Autodesk Fusion 360 part; units mm, degrees
(part 4 of 6)
sketch "Skizze7" plane through (0, 0, 0) normal (0, 1, 0) x (1, 0, 0)
  spline S0 degree 5 poles (100, -0.15) (99.9698, -0.1532) (99.9069, -0.1598) (99.8054, -0.1706) (99.6556, -0.1869) (99.4448, -0.2102) (99.2115, -0.2365) (98.9585, -0.2653) (98.6894, -0.2962) (98.4089, -0.3287) (98.1211, -0.3622) (97.8299, -0.3962) (97.5376, -0.4305) (97.2451, -0.4648) (96.9524, -0.4991) (96.6588, -0.5333) (96.3636, -0.5675) (96.0663, -0.6017) (95.7669, -0.6359) (95.4657, -0.6701) (95.1634, -0.7042) (94.8605, -0.7382) (94.5577, -0.7721) (94.2552, -0.8059) (93.9531, -0.8396) (93.6512, -0.8731) (93.3495, -0.9065) (93.0476, -0.9398) (92.7455, -0.973) (92.4431, -1.0061) (92.1403, -1.0391) (91.8374, -1.072) (91.5343, -1.1047) (91.2312, -1.1374) (90.9281, -1.1699) (90.625, -1.2023) (90.322, -1.2347) (90.019, -1.267) (89.7161, -1.2992) (89.4132, -1.3314) (89.1102, -1.3636) (88.8072, -1.3956) (88.5041, -1.4276) (88.2009, -1.4595) (87.8975, -1.4912) (87.5941, -1.5229) (87.2907, -1.5544) (86.9871, -1.5858) (86.6836, -1.6171) (86.3801, -1.6483) (86.0766, -1.6795) (85.7732, -1.7106) (85.4697, -1.7417) (85.1663, -1.7727) (84.8628, -1.8038) (84.5593, -1.8349) (84.2557, -1.8659) (83.9521, -1.8968) (83.6485, -1.9277) (83.3449, -1.9586) (83.0413, -1.9893) (82.7378, -2.02) (82.4342, -2.0506) (82.1306, -2.0811) (81.827, -2.1116) (81.5234, -2.142) (81.2197, -2.1725) (80.9161, -2.2029) (80.6124, -2.2334) (80.3086, -2.2637) (80.0049, -2.294) (79.7012, -2.3242) (79.3975, -2.3544) (79.0939, -2.3844) (78.7902, -2.4144) (78.4864, -2.4443) (78.1827, -2.4742) (77.8789, -2.5041) (77.5751, -2.5339) (77.2713, -2.5637) (76.9674, -2.5935) (76.6636, -2.6233) (76.3598, -2.6531) (76.0561, -2.6829) (75.7523, -2.7126) (75.4486, -2.7423) (75.1449, -2.7719) (74.8412, -2.8013) (74.5375, -2.8308) (74.2337, -2.8601) (73.93, -2.8894) (73.6262, -2.9186) (73.3225, -2.9478) (73.0187, -2.977) (72.7151, -3.0062) (72.4114, -3.0354) (72.1077, -3.0646) (71.8041, -3.0937) (71.5005, -3.1226) (71.1968, -3.1514) (70.8931, -3.1801) (70.5894, -3.2087) (70.2857, -3.2372) (69.982, -3.2656) (69.6783, -3.294) (69.3747, -3.3223) (69.071, -3.3505) (68.7674, -3.3787) (68.4638, -3.4069) (68.1603, -3.435) (67.8567, -3.463) (67.5532, -3.491) (67.2497, -3.5189) (66.9462, -3.5467) (66.6426, -3.5745) (66.3391, -3.6021) (66.0355, -3.6297) (65.7319, -3.6571) (65.4284, -3.6845) (65.1248, -3.7116) (64.8213, -3.7386) (64.5177, -3.7655) (64.2142, -3.7922) (63.9107, -3.8188) (63.6073, -3.8453) (63.3038, -3.8717) (63.0003, -3.8982) (62.6968, -3.9245) (62.3932, -3.9509) (62.0897, -3.9771) (61.7862, -4.0033) (61.4827, -4.0293) (61.1792, -4.0552) (60.8757, -4.0809) (60.5722, -4.1065) (60.2688, -4.1319) (59.9654, -4.1571) (59.662, -4.1823) (59.3586, -4.2073) (59.0552, -4.2323) (58.7519, -4.257) (58.4485, -4.2817) (58.1451, -4.3062) (57.8416, -4.3305) (57.5382, -4.3547) (57.2348, -4.3788) (56.9313, -4.4028) (56.6279, -4.4267) (56.3246, -4.4505) (56.0212, -4.4742) (55.7178, -4.4977) (55.4145, -4.5211) (55.1112, -4.5442) (54.8078, -4.5671) (54.5044, -4.5897) (54.201, -4.6121) (53.8976, -4.6343) (53.5942, -4.6565) (53.2908, -4.6785) (52.9874, -4.7005) (52.6841, -4.7225) (52.3808, -4.7443) (52.0775, -4.7661) (51.7742, -4.7877) (51.4709, -4.809) (51.1676, -4.83) (50.8643, -4.8508) (50.561, -4.8712) (50.2577, -4.8915) (49.9545, -4.9115) (49.6512, -4.9314) (49.348, -4.9511) (49.0448, -4.9707) (48.7416, -4.9902) (48.4384, -5.0096) (48.1352, -5.0289) (47.832, -5.048) (47.5287, -5.067) (47.2255, -5.0857) (46.9222, -5.1042) (46.619, -5.1224) (46.3158, -5.1403) (46.0126, -5.1578) (45.7095, -5.1752) (45.4065, -5.1922) (45.1034, -5.2091) (44.8004, -5.2257) (44.4974, -5.2422) (44.1943, -5.2585) (43.8913, -5.2747) (43.5883, -5.2906) (43.2852, -5.3063) (42.9822, -5.3218) (42.6791, -5.3371) (42.376, -5.352) (42.0729, -5.3668) (41.7699, -5.3812) (41.4668, -5.3954) (41.1639, -5.4093) (40.8609, -5.423) (40.558, -5.4364) (40.2551, -5.4495) (39.9523, -5.4623) (39.6494, -5.4749) (39.3467, -5.4871) (39.0439, -5.4992) (38.7411, -5.511) (38.4384, -5.5225) (38.1357, -5.5338) (37.833, -5.5448) (37.5303, -5.5556) (37.2276, -5.566) (36.9249, -5.5762) (36.6223, -5.586) (36.3195, -5.5955) (36.0169, -5.6046) (35.7142, -5.6134) (35.4116, -5.6218) (35.109, -5.6299) (34.8065, -5.6376) (34.5041, -5.645) (34.2017, -5.6521) (33.8993, -5.6588) (33.597, -5.6653) (33.2947, -5.6714) (32.9923, -5.6771) (32.69, -5.6826) (32.3877, -5.6877) (32.0854, -5.6924) (31.7831, -5.6968) (31.4809, -5.7008) (31.1788, -5.7044) (30.8767, -5.7077) (30.5747, -5.7105) (30.2727, -5.713) (29.9708, -5.7151) (29.6689, -5.7167) (29.367, -5.718) (29.0651, -5.7188) (28.7633, -5.7192) (28.4615, -5.7192) (28.1597, -5.7188) (27.858, -5.718) (27.5564, -5.7168) (27.2548, -5.7152) (26.9533, -5.7132) (26.652, -5.7108) (26.3507, -5.708) (26.0495, -5.7047) (25.7484, -5.701) (25.4474, -5.6967) (25.1464, -5.6918) (24.8455, -5.6863) (24.5447, -5.6803) (24.2439, -5.6737) (23.9432, -5.6666) (23.6427, -5.659) (23.3422, -5.6509) (23.0419, -5.6424) (22.7418, -5.6333) (22.4418, -5.6237) (22.1419, -5.6136) (21.8422, -5.6028) (21.5426, -5.5913) (21.2432, -5.5792) (20.9438, -5.5665) (20.6446, -5.5531) (20.3455, -5.5391) (20.0466, -5.5244) (19.7477, -5.5091) (19.4491, -5.4931) (19.1507, -5.4765) (18.8524, -5.4591) (18.5545, -5.4409) (18.2568, -5.422) (17.9594, -5.4023) (17.6622, -5.3817) (17.3652, -5.3603) (17.0684, -5.3381) (16.7718, -5.315) (16.4753, -5.2911) (16.1791, -5.2663) (15.8831, -5.2407) (15.5874, -5.2142) (15.2919, -5.1867) (14.9968, -5.1584) (14.702, -5.1291) (14.4076, -5.0988) (14.1136, -5.0674) (13.8201, -5.0351) (13.5269, -5.0016) (13.2341, -4.9671) (12.9417, -4.9315) (12.6498, -4.8948) (12.3582, -4.857) (12.0671, -4.818) (11.7764, -4.7779) (11.4862, -4.7365) (11.1965, -4.6938) (10.9075, -4.6497) (10.6192, -4.6043) (10.3315, -4.5575) (10.0447, -4.5093) (9.7585, -4.4596) (9.4732, -4.4085) (9.1887, -4.356) (8.9051, -4.302) (8.6225, -4.2465) (8.3408, -4.1894) (8.0602, -4.1305) (7.7808, -4.0699) (7.5027, -4.0075) (7.226, -3.9431) (6.9507, -3.8769) (6.677, -3.8087) (6.4051, -3.7385) (6.135, -3.6664) (5.8669, -3.5922) (5.6011, -3.5159) (5.3377, -3.4374) (5.0769, -3.3567) (4.819, -3.2736) (4.5643, -3.1883) (4.3131, -3.1008) (4.0657, -3.011) (3.8225, -2.9191) (3.5839, -2.8252) (3.3505, -2.7292) (3.1226, -2.6313) (2.9008, -2.5315) (2.6856, -2.4301) (2.4774, -2.3275) (2.2767, -2.2241) (2.0839, -2.1203) (1.8992, -2.0164) (1.7229, -1.9124) (1.5554, -1.8083) (1.3968, -1.7039) (1.2471, -1.5995) (1.1063, -1.4957) (0.9742, -1.3933) (0.8506, -1.2926) (0.7354, -1.1923) (0.6286, -1.0909) (0.53, -0.9884) (0.4394, -0.888) (0.3563, -0.7927) (0.281, -0.6986) (0.2138, -0.5963) (0.1548, -0.487) (0.1038, -0.3939) (0.0606, -0.3221) (0.0271, -0.2204) (0.0055, -0.0625) (-0.0028, 0.0091) (-0.0003, -0.0252) (0.0079, 0.0969) (0.0316, 0.2301) (0.0746, 0.3075) (0.1323, 0.3792) (0.2013, 0.4693) (0.2805, 0.5567) (0.3689, 0.6311) (0.4651, 0.7007) (0.5684, 0.7731) (0.6792, 0.8469) (0.798, 0.9188) (0.925, 0.9876) (1.0603, 1.0544) (1.2038, 1.1205) (1.3558, 1.1861) (1.5166, 1.2512) (1.6866, 1.3155) (1.8657, 1.3788) (2.0541, 1.441) (2.2515, 1.5019) (2.4577, 1.5615) (2.6724, 1.6197) (2.8953, 1.6763) (3.1259, 1.7312) (3.3638, 1.7844) (3.6084, 1.8358) (3.8593, 1.8852) (4.116, 1.9326) (4.3778, 1.978) (4.6442, 2.0215) (4.9147, 2.0631) (5.1886, 2.1031) (5.4656, 2.1415) (5.7452, 2.1784) (6.0271, 2.2138) (6.311, 2.2478) (6.5966, 2.2804) (6.8839, 2.3115) (7.1726, 2.3413) (7.4625, 2.3698) (7.7535, 2.3969) (8.0455, 2.4229) (8.3383, 2.4477) (8.6319, 2.4715) (8.926, 2.4943) (9.2208, 2.5161) (9.516, 2.5371) (9.8118, 2.5573) (10.1081, 2.5766) (10.4048, 2.5951) (10.702, 2.6128) (10.9995, 2.6297) (11.2974, 2.6459) (11.5957, 2.6612) (11.8942, 2.6758) (12.1931, 2.6897) (12.4922, 2.7029) (12.7915, 2.7155) (13.0911, 2.7274) (13.3908, 2.7387) (13.6908, 2.7495) (13.991, 2.7597) (14.2914, 2.7694) (14.592, 2.7786) (14.8927, 2.7873) (15.1936, 2.7956) (15.4947, 2.8034) (15.7959, 2.8107) (16.0972, 2.8176) (16.3986, 2.8241) (16.7001, 2.8301) (17.0017, 2.8357) (17.3034, 2.8408) (17.6052, 2.8455) (17.9071, 2.8497) (18.2091, 2.8535) (18.5113, 2.8569) (18.8135, 2.8599) (19.1159, 2.8626) (19.4183, 2.8649) (19.7208, 2.867) (20.0233, 2.8687) (20.3259, 2.8702) (20.6285, 2.8714) (20.9313, 2.8723) (21.2341, 2.8729) (21.537, 2.8732) (21.8401, 2.8731) (22.1432, 2.8727) (22.4464, 2.872) (22.7496, 2.8711) (23.0529, 2.87) (23.3562, 2.8687) (23.6595, 2.8672) (23.9628, 2.8655) (24.2662, 2.8635) (24.5695, 2.8612) (24.873, 2.8586) (25.1764, 2.8557) (25.4799, 2.8526) (25.7834, 2.8491) (26.087, 2.8455) (26.3906, 2.8417) (26.6942, 2.8377) (26.9979, 2.8335) (27.3016, 2.8292) (27.6053, 2.8247) (27.909, 2.8199) (28.2128, 2.815) (28.5166, 2.8098) (28.8204, 2.8044) (29.1243, 2.7989) (29.4282, 2.7931) (29.7322, 2.7872) (30.0362, 2.7811) (30.3402, 2.7749) (30.6443, 2.7685) (30.9483, 2.762) (31.2524, 2.7553) (31.5565, 2.7485) (31.8605, 2.7415) (32.1646, 2.7343) (32.4688, 2.727) (32.7729, 2.7194) (33.0771, 2.7116) (33.3814, 2.7037) (33.6857, 2.6956) (33.99, 2.6873) (34.2943, 2.679) (34.5986, 2.6706) (34.9029, 2.6621) (35.2072, 2.6536) (35.5115, 2.6449) (35.8158, 2.6362) (36.1201, 2.6272) (36.4244, 2.6181) (36.7287, 2.6088) (37.033, 2.5992) (37.3374, 2.5896) (37.6418, 2.5797) (37.9462, 2.5698) (38.2506, 2.5597) (38.555, 2.5497) (38.8595, 2.5395) (39.1639, 2.5293) (39.4684, 2.519) (39.7729, 2.5086) (40.0774, 2.4981) (40.382, 2.4874) (40.6865, 2.4767) (40.9911, 2.4658) (41.2956, 2.4548) (41.6001, 2.4437) (41.9046, 2.4325) (42.2091, 2.4213) (42.5136, 2.4099) (42.8182, 2.3985) (43.1227, 2.3871) (43.4273, 2.3756) (43.7319, 2.3641) (44.0365, 2.3525) (44.3412, 2.3407) (44.6458, 2.3289) (44.9504, 2.3169) (45.255, 2.3047) (45.5596, 2.2923) (45.8641, 2.2798) (46.1687, 2.2673) (46.4734, 2.2546) (46.778, 2.2419) (47.0827, 2.2291) (47.3874, 2.2163) (47.6921, 2.2036) (47.9968, 2.1909) (48.3015, 2.1781) (48.6061, 2.1654) (48.9108, 2.1526) (49.2155, 2.1396) (49.5202, 2.1265) (49.8248, 2.1133) (50.1295, 2.0999) (50.4341, 2.0863) (50.7388, 2.0725) (51.0434, 2.0588) (51.3481, 2.0449) (51.6528, 2.0311) (51.9575, 2.0173) (52.2622, 2.0035) (52.567, 1.9897) (52.8718, 1.9759) (53.1766, 1.962) (53.4814, 1.948) (53.7863, 1.9339) (54.0912, 1.9197) (54.396, 1.9054) (54.7008, 1.891) (55.0055, 1.8766) (55.3102, 1.862) (55.6149, 1.8475) (55.9196, 1.8329) (56.2244, 1.8183) (56.5292, 1.8037) (56.834, 1.789) (57.139, 1.7744) (57.4439, 1.7597) (57.7489, 1.7449) (58.0538, 1.7301) (58.3586, 1.7151) (58.6635, 1.7001) (58.9683, 1.685) (59.273, 1.6699) (59.5778, 1.6547) (59.8826, 1.6395) (60.1875, 1.6242) (60.4923, 1.609) (60.7972, 1.5937) (61.1022, 1.5784) (61.4071, 1.5631) (61.7121, 1.5478) (62.017, 1.5324) (62.322, 1.5169) (62.627, 1.5014) (62.932, 1.4859) (63.237, 1.4704) (63.5421, 1.4549) (63.8472, 1.4393) (64.1522, 1.4237) (64.4573, 1.408) (64.7624, 1.3923) (65.0675, 1.3765) (65.3726, 1.3607) (65.6776, 1.3449) (65.9827, 1.3291) (66.2877, 1.3133) (66.5928, 1.2974) (66.8979, 1.2816) (67.203, 1.2658) (67.5081, 1.2501) (67.8131, 1.2342) (68.1182, 1.2184) (68.4232, 1.2026) (68.7282, 1.1867) (69.0331, 1.1709) (69.3381, 1.1551) (69.643, 1.1393) (69.948, 1.1236) (70.253, 1.1079) (70.558, 1.0923) (70.863, 1.0767) (71.168, 1.0611) (71.4729, 1.0454) (71.7779, 1.0298) (72.0828, 1.0141) (72.3876, 0.9984) (72.6925, 0.9828) (72.9974, 0.9672) (73.3023, 0.9516) (73.6072, 0.9362) (73.9121, 0.9209) (74.217, 0.9056) (74.5219, 0.8904) (74.8268, 0.8753) (75.1316, 0.8602) (75.4364, 0.8452) (75.7411, 0.8301) (76.0458, 0.815) (76.3504, 0.7999) (76.6551, 0.7847) (76.9597, 0.7696) (77.2643, 0.7545) (77.569, 0.7396) (77.8736, 0.7247) (78.1782, 0.7101) (78.4828, 0.6956) (78.7874, 0.6812) (79.092, 0.667) (79.3966, 0.6529) (79.7011, 0.6389) (80.0055, 0.6249) (80.31, 0.6109) (80.6144, 0.5969) (80.9188, 0.583) (81.2231, 0.5692) (81.5274, 0.5556) (81.8317, 0.5421) (82.136, 0.5288) (82.4402, 0.5157) (82.7444, 0.5027) (83.0486, 0.4897) (83.3527, 0.4769) (83.6567, 0.4641) (83.9608, 0.4514) (84.2648, 0.4388) (84.5688, 0.4263) (84.8728, 0.414) (85.1769, 0.4018) (85.4809, 0.3898) (85.7849, 0.378) (86.0889, 0.3665) (86.3928, 0.3551) (86.6966, 0.344) (87.0004, 0.3332) (87.3041, 0.3225) (87.6078, 0.3119) (87.9114, 0.3015) (88.2151, 0.2912) (88.5187, 0.281) (88.8224, 0.271) (89.126, 0.2612) (89.4295, 0.2516) (89.7329, 0.2423) (90.0362, 0.2333) (90.3395, 0.2246) (90.6426, 0.2162) (90.9458, 0.2081) (91.2489, 0.2001) (91.5521, 0.1924) (91.8553, 0.1848) (92.1584, 0.1775) (92.4612, 0.1704) (92.7638, 0.1635) (93.0659, 0.1571) (93.3677, 0.151) (93.6691, 0.1453) (93.9705, 0.1401) (94.2719, 0.1353) (94.5735, 0.1308) (94.8753, 0.1267) (95.1771, 0.123) (95.4782, 0.1197) (95.7781, 0.1167) (96.0762, 0.1143) (96.3721, 0.1124) (96.6657, 0.111) (96.9575, 0.1103) (97.2484, 0.1103) (97.5392, 0.1111) (97.83, 0.1126) (98.12, 0.1148) (98.407, 0.1178) (98.6872, 0.1213) (98.9562, 0.1253) (99.2095, 0.1298) (99.4431, 0.1345) (99.6545, 0.1395) (99.8047, 0.1436) (99.9066, 0.1468) (99.9697, 0.1489) (100, 0.15) knots 0 0 0 0 0 0 0.00142857 0.00285714 0.00428571 0.00571429 0.00714286 0.00857143 0.01 0.01142857 0.01285714 0.01428571 0.01571429 0.01714286 0.01857143 0.02 0.02142857 0.02285714 0.02428571 0.02571429 0.02714286 0.02857143 0.03 0.03142857 0.03285714 0.03428571 0.03571429 0.03714286 0.03857143 0.04 0.04142857 0.04285714 0.04428571 0.04571429 0.04714286 0.04857143 0.05 0.05142857 0.05285714 0.05428571 0.05571429 0.05714286 0.05857143 0.06 0.06142857 0.06285714 0.06428571 0.06571429 0.06714286 0.06857143 0.07 0.07142857 0.07285714 0.07428571 0.07571429 0.07714286 0.07857143 0.08 0.08142857 0.08285714 0.08428571 0.08571429 0.08714286 0.08857143 0.09 0.09142857 0.09285714 0.09428571 0.09571429 0.09714286 0.09857143 0.1 0.10142857 0.10285714 0.10428571 0.10571429 0.10714286 0.10857143 0.11 0.11142857 0.11285714 0.11428571 0.11571429 0.11714286 0.11857143 0.12 0.12142857 0.12285714 0.12428571 0.12571429 0.12714286 0.12857143 0.13 0.13142857 0.13285714 0.13428571 0.13571429 0.13714286 0.13857143 0.14 0.14142857 0.14285714 0.14428571 0.14571429 0.14714286 0.14857143 0.15 0.15142857 0.15285714 0.15428571 0.15571429 0.15714286 0.15857143 0.16 0.16142857 0.16285714 0.16428571 0.16571429 0.16714286 0.16857143 0.17 0.17142857 0.17285714 0.17428571 0.17571429 0.17714286 0.17857143 0.18 0.18142857 0.18285714 0.18428571 0.18571429 0.18714286 0.18857143 0.19 0.19142857 0.19285714 0.19428571 0.19571429 0.19714286 0.19857143 0.2 0.20142857 0.20285714 0.20428571 0.20571429 0.20714286 0.20857143 0.21 0.21142857 0.21285714 0.21428571 0.21571429 0.21714286 0.21857143 0.22 0.22142857 0.22285714 0.22428571 0.22571429 0.22714286 0.22857143 0.23 0.23142857 0.23285714 0.23428571 0.23571429 0.23714286 0.23857143 0.24 0.24142857 0.24285714 0.24428571 0.24571429 0.24714286 0.24857143 0.25 0.25142857 0.25285714 0.25428571 0.25571429 0.25714286 0.25857143 0.26 0.26142857 0.26285714 0.26428571 0.26571429 0.26714286 0.26857143 0.27 0.27142857 0.27285714 0.27428571 0.27571429 0.27714286 0.27857143 0.28 0.28142857 0.28285714 0.28428571 0.28571429 0.28714286 0.28857143 0.29 0.29142857 0.29285714 0.29428571 0.29571429 0.29714286 0.29857143 0.3 0.30142857 0.30285714 0.30428571 0.30571429 0.30714286 0.30857143 0.31 0.31142857 0.31285714 0.31428571 0.31571429 0.31714286 0.31857143 0.32 0.32142857 0.32285714 0.32428571 0.32571429 0.32714286 0.32857143 0.33 0.33142857 0.33285714 0.33428571 0.33571429 0.33714286 0.33857143 0.34 0.34142857 0.34285714 0.34428571 0.34571429 0.34714286 0.34857143 0.35 0.35142857 0.35285714 0.35428571 0.35571429 0.35714286 0.35857143 0.36 0.36142857 0.36285714 0.36428571 0.36571429 0.36714286 0.36857143 0.37 0.37142857 0.37285714 0.37428571 0.37571429 0.37714286 0.37857143 0.38 0.38142857 0.38285714 0.38428571 0.38571429 0.38714286 0.38857143 0.39 0.39142857 0.39285714 0.39428571 0.39571429 0.39714286 0.39857143 0.4 0.40142857 0.40285714 0.40428571 0.40571429 0.40714286 0.40857143 0.41 0.41142857 0.41285714 0.41428571 0.41571429 0.41714286 0.41857143 0.42 0.42142857 0.42285714 0.42428571 0.42571429 0.42714286 0.42857143 0.43 0.43142857 0.43285714 0.43428571 0.43571429 0.43714286 0.43857143 0.44 0.44142857 0.44285714 0.44428571 0.44571429 0.44714286 0.44857143 0.45 0.45142857 0.45285714 0.45428571 0.45571429 0.45714286 0.45857143 0.46 0.46142857 0.46285714 0.46428571 0.46571429 0.46714286 0.46857143 0.47 0.47142857 0.47285714 0.47428571 0.47571429 0.47714286 0.47857143 0.48 0.48142857 0.48285714 0.48428571 0.48571429 0.48714286 0.48857143 0.49 0.49142857 0.49285714 0.49428571 0.49571429 0.49714286 0.49857143 0.5 0.50142857 0.50285714 0.50428571 0.50571429 0.50714286 0.50857143 0.51 0.51142857 0.51285714 0.51428571 0.51571429 0.51714286 0.51857143 0.52 0.52142857 0.52285714 0.52428571 0.52571429 0.52714286 0.52857143 0.53 0.53142857 0.53285714 0.53428571 0.53571429 0.53714286 0.53857143 0.54 0.54142857 0.54285714 0.54428571 0.54571429 0.54714286 0.54857143 0.55 0.55142857 0.55285714 0.55428571 0.55571429 0.55714286 0.55857143 0.56 0.56142857 0.56285714 0.56428571 0.56571429 0.56714286 0.56857143 0.57 0.57142857 0.57285714 0.57428571 0.57571429 0.57714286 0.57857143 0.58 0.58142857 0.58285714 0.58428571 0.58571429 0.58714286 0.58857143 0.59 0.59142857 0.59285714 0.59428571 0.59571429 0.59714286 0.59857143 0.6 0.60142857 0.60285714 0.60428571 0.60571429 0.60714286 0.60857143 0.61 0.61142857 0.61285714 0.61428571 0.61571429 0.61714286 0.61857143 0.62 0.62142857 0.62285714 0.62428571 0.62571429 0.62714286 0.62857143 0.63 0.63142857 0.63285714 0.63428571 0.63571429 0.63714286 0.63857143 0.64 0.64142857 0.64285714 0.64428571 0.64571429 0.64714286 0.64857143 0.65 0.65142857 0.65285714 0.65428571 0.65571429 0.65714286 0.65857143 0.66 0.66142857 0.66285714 0.66428571 0.66571429 0.66714286 0.66857143 0.67 0.67142857 0.67285714 0.67428571 0.67571429 0.67714286 0.67857143 0.68 0.68142857 0.68285714 0.68428571 0.68571429 0.68714286 0.68857143 0.69 0.69142857 0.69285714 0.69428571 0.69571429 0.69714286 0.69857143 0.7 0.70142857 0.70285714 0.70428571 0.70571429 0.70714286 0.70857143 0.71 0.71142857 0.71285714 0.71428571 0.71571429 0.71714286 0.71857143 0.72 0.72142857 0.72285714 0.72428571 0.72571429 0.72714286 0.72857143 0.73 0.73142857 0.73285714 0.73428571 0.73571429 0.73714286 0.73857143 0.74 0.74142857 0.74285714 0.74428571 0.74571429 0.74714286 0.74857143 0.75 0.75142857 0.75285714 0.75428571 0.75571429 0.75714286 0.75857143 0.76 0.76142857 0.76285714 0.76428571 0.76571429 0.76714286 0.76857143 0.77 0.77142857 0.77285714 0.77428571 0.77571429 0.77714286 0.77857143 0.78 0.78142857 0.78285714 0.78428571 0.78571429 0.78714286 0.78857143 0.79 0.79142857 0.79285714 0.79428571 0.79571429 0.79714286 0.79857143 0.8 0.80142857 0.80285714 0.80428571 0.80571429 0.80714286 0.80857143 0.81 0.81142857 0.81285714 0.81428571 0.81571429 0.81714286 0.81857143 0.82 0.82142857 0.82285714 0.82428571 0.82571429 0.82714286 0.82857143 0.83 0.83142857 0.83285714 0.83428571 0.83571429 0.83714286 0.83857143 0.84 0.84142857 0.84285714 0.84428571 0.84571429 0.84714286 0.84857143 0.85 0.85142857 0.85285714 0.85428571 0.85571429 0.85714286 0.85857143 0.86 0.86142857 0.86285714 0.86428571 0.86571429 0.86714286 0.86857143 0.87 0.87142857 0.87285714 0.87428571 0.87571429 0.87714286 0.87857143 0.88 0.88142857 0.88285714 0.88428571 0.88571429 0.88714286 0.88857143 0.89 0.89142857 0.89285714 0.89428571 0.89571429 0.89714286 0.89857143 0.9 0.90142857 0.90285714 0.90428571 0.90571429 0.90714286 0.90857143 0.91 0.91142857 0.91285714 0.91428571 0.91571429 0.91714286 0.91857143 0.92 0.92142857 0.92285714 0.92428571 0.92571429 0.92714286 0.92857143 0.93 0.93142857 0.93285714 0.93428571 0.93571429 0.93714286 0.93857143 0.94 0.94142857 0.94285714 0.94428571 0.94571429 0.94714286 0.94857143 0.95 0.95142857 0.95285714 0.95428571 0.95571429 0.95714286 0.95857143 0.96 0.96142857 0.96285714 0.96428571 0.96571429 0.96714286 0.96857143 0.97 0.97142857 0.97285714 0.97428571 0.97571429 0.97714286 0.97857143 0.98 0.98142857 0.98285714 0.98428571 0.98571429 0.98714286 0.98857143 0.99 0.99142857 0.99285714 0.99428571 0.99571429 0.99714286 0.99857143 1 1 1 1 1 1
  line L0 (100, 0.15) -> (100, -0.15)
  point P0 (99.314, -0.225)
  point P1 (97.986, -0.378)
  point P2 (96.428, -0.56)
  point P3 (94.791, -0.746)
  point P4 (93.136, -0.93)
  point P5 (91.476, -1.111)
  point P6 (89.812, -1.289)
  point P7 (88.148, -1.465)
  point P8 (86.48, -1.638)
  point P9 (84.812, -1.809)
  point P10 (83.143, -1.979)
  point P11 (81.474, -2.147)
  point P12 (79.804, -2.314)
  point P13 (78.134, -2.479)
  point P14 (76.463, -2.643)
  point P15 (74.793, -2.806)
  point P16 (73.123, -2.967)
  point P17 (71.454, -3.127)
  point P18 (69.785, -3.284)
  point P19 (68.117, -3.439)
  point P20 (66.45, -3.592)
  point P21 (64.783, -3.742)
  point P22 (63.117, -3.888)
  point P23 (61.451, -4.032)
  point P24 (59.786, -4.172)
  point P25 (58.122, -4.308)
  point P26 (56.458, -4.44)
  point P27 (54.795, -4.568)
  point P28 (53.132, -4.69)
  point P29 (51.47, -4.809)
  point P30 (49.809, -4.921)
  point P31 (48.149, -5.028)
  point P32 (46.489, -5.13)
  point P33 (44.831, -5.224)
  point P34 (43.174, -5.312)
  point P35 (41.517, -5.393)
  point P36 (39.862, -5.466)
  point P37 (38.209, -5.531)
  point P38 (36.557, -5.588)
  point P39 (34.906, -5.635)
  point P40 (33.258, -5.672)
  point P41 (31.611, -5.699)
  point P42 (29.967, -5.715)
  point P43 (28.325, -5.719)
  point P44 (26.686, -5.711)
  point P45 (25.052, -5.69)
  point P46 (23.422, -5.653)
  point P47 (21.799, -5.601)
  point P48 (20.183, -5.531)
  point P49 (18.575, -5.442)
  point P50 (16.979, -5.331)
  point P51 (15.393, -5.196)
  point P52 (13.822, -5.035)
  point P53 (12.27, -4.845)
  point P54 (10.739, -4.623)
  point P55 (9.239, -4.365)
  point P56 (7.779, -4.069)
  point P57 (6.375, -3.73)
  point P58 (5.052, -3.348)
  point P59 (3.848, -2.928)
  point P60 (2.814, -2.49)
  point P61 (1.992, -2.068)
  point P62 (1.38, -1.691)
  point P63 (0.938, -1.363)
  point P64 (0.619, -1.079)
  point P65 (0.387, -0.827)
  point P66 (0.219, -0.6)
  point P67 (0.102, -0.392)
  point P68 (0.028, -0.198)
  point P69 (0, -0.016)
  point P70 (0.022, 0.161)
  point P71 (0.102, 0.34)
  point P72 (0.243, 0.513)
  point P73 (0.44, 0.682)
  point P74 (0.698, 0.857)
  point P75 (1.039, 1.043)
  point P76 (1.496, 1.242)
  point P77 (2.124, 1.462)
  point P78 (2.98, 1.696)
  point P79 (4.089, 1.927)
  point P80 (5.414, 2.134)
  point P81 (6.873, 2.31)
  point P82 (8.406, 2.453)
  point P83 (9.978, 2.568)
  point P84 (11.575, 2.66)
  point P85 (13.189, 2.731)
  point P86 (14.815, 2.785)
  point P87 (16.45, 2.825)
  point P88 (18.091, 2.852)
  point P89 (19.738, 2.867)
  point P90 (21.389, 2.873)
  point P91 (23.045, 2.87)
  point P92 (24.703, 2.86)
  point P93 (26.363, 2.842)
  point P94 (28.025, 2.818)
  point P95 (29.689, 2.788)
  point P96 (31.355, 2.753)
  point P97 (33.022, 2.713)
  point P98 (34.691, 2.668)
  point P99 (36.36, 2.62)
  point P100 (38.03, 2.567)
  point P101 (39.701, 2.511)
  point P102 (41.373, 2.452)
  point P103 (43.045, 2.39)
  point P104 (44.718, 2.326)
  point P105 (46.391, 2.258)
  point P106 (48.065, 2.188)
  point P107 (49.739, 2.117)
  point P108 (51.413, 2.042)
  point P109 (53.088, 1.966)
  point P110 (54.764, 1.888)
  point P111 (56.439, 1.808)
  point P112 (58.116, 1.727)
  point P113 (59.792, 1.644)
  point P114 (61.469, 1.56)
  point P115 (63.147, 1.475)
  point P116 (64.826, 1.389)
  point P117 (66.505, 1.302)
  point P118 (68.184, 1.215)
  point P119 (69.862, 1.128)
  point P120 (71.54, 1.042)
  point P121 (73.217, 0.956)
  point P122 (74.894, 0.872)
  point P123 (76.569, 0.789)
  point P124 (78.243, 0.707)
  point P125 (79.916, 0.629)
  point P126 (81.587, 0.553)
  point P127 (83.256, 0.481)
  point P128 (84.923, 0.412)
  point P129 (86.589, 0.348)
  point P130 (88.252, 0.29)
  point P131 (89.913, 0.237)
  point P132 (91.57, 0.192)
  point P133 (93.221, 0.154)
  point P134 (94.86, 0.127)
  point P135 (96.471, 0.112)
  point P136 (98.001, 0.114)
  point P137 (99.315, 0.132)
surface "Profilschnitt_R3" add patch profiles "Skizze7" section 1 separate body makes body 7
scale "Profiltiefe_R3" factor 1.05 about (0, 0, 0) bodies 7
move_body "Station_R3" bodies 7 to x (1, 0, 0) y (0, 1, 0) z (0, 0, 1) at (0, 1279.8142, 21.2919)
loft "Fluegelsegment_L1" add section 1 face at (94.3234, 0, 0.5477) section 2 face at (94.3234, -60, 0.5477) separate body on bodies 1 2 makes body 8
loft "Fluegelsegment_L2" add section 1 face at (94.3234, -60, 0.5477) section 2 face at (61.0067, -669.9071, 11.0551) separate body on bodies 2 3 makes body 9
loft "Fluegelsegment_L3" add section 1 face at (61.0067, -669.9071, 11.0551) section 2 face at (31.5807, -1279.8142, 21.5024) separate body on bodies 3 4 makes body 10
loft "Fluegelsegment_R1" add section 1 face at (94.3234, 0, 0.5477) section 2 face at (94.3234, 60, 0.5477) separate body on bodies 1 5 makes body 11
loft "Fluegelsegment_R2" add section 1 face at (94.3234, 60, 0.5477) section 2 face at (61.0067, 669.9071, 11.0551) separate body on bodies 5 6 makes body 12
loft "Fluegelsegment_R3" add section 1 face at (61.0067, 669.9071, 11.0551) section 2 face at (31.5807, 1279.8142, 21.5024) separate body on bodies 6 7 makes body 13
combine "Alle_Fluegelsegmente_verbinden" operation add target body 8 tool bodies 9 10 11 12 13
delete_body "Körper entfernen1" bodies 1
delete_body "Körper entfernen2" bodies 2
delete_body "Körper entfernen3" bodies 3
delete_body "Körper entfernen4" bodies 4
delete_body "Körper entfernen5" bodies 5
delete_body "Körper entfernen6" bodies 6
delete_body "Körper entfernen7" bodies 7
sketch "Skizze8" plane through (0, 0, 0) normal (0, 1, 0) x (1, 0, 0)
  spline S0 degree 5 poles (100, 0) (99.9599, -0.0026) (99.8783, -0.0078) (99.7514, -0.0159) (99.5736, -0.0272) (99.3368, -0.0422) (99.0859, -0.058) (98.8215, -0.0747) (98.5446, -0.0922) (98.2562, -0.1105) (97.9576, -0.1296) (97.6501, -0.1494) (97.3347, -0.1698) (97.0124, -0.1908) (96.6841, -0.2122) (96.3507, -0.2339) (96.013, -0.256) (95.6718, -0.2783) (95.328, -0.3008) (94.9821, -0.3235) (94.6349, -0.3465) (94.2867, -0.3695) (93.9378, -0.3928) (93.5884, -0.4161) (93.2386, -0.4396) (92.8883, -0.4632) (92.5376, -0.4869) (92.1865, -0.5106) (91.8352, -0.5344) (91.4836, -0.5582) (91.1319, -0.5821) (90.7802, -0.606) (90.4285, -0.6299) (90.0769, -0.6539) (89.7253, -0.678) (89.3737, -0.7023) (89.022, -0.7267) (88.6703, -0.7512) (88.3186, -0.7759) (87.9668, -0.8006) (87.6149, -0.8254) (87.263, -0.8502) (86.9111, -0.8749) (86.5592, -0.8995) (86.2073, -0.9241) (85.8554, -0.9488) (85.5035, -0.9735) (85.1516, -0.9983) (84.7997, -1.0232) (84.4478, -1.0482) (84.096, -1.0733) (83.7441, -1.0984) (83.3921, -1.1236) (83.0402, -1.1487) (82.6882, -1.1738) (82.3362, -1.1989) (81.9842, -1.2239) (81.6322, -1.2489) (81.2802, -1.2739) (80.9282, -1.2989) (80.5763, -1.3239) (80.2243, -1.3489) (79.8723, -1.374) (79.5203, -1.3991) (79.1682, -1.4243) (78.8161, -1.4495) (78.464, -1.4747) (78.1119, -1.5) (77.7598, -1.5252) (77.4078, -1.5505) (77.0559, -1.5758) (76.704, -1.601) (76.3522, -1.6263) (76.0003, -1.6515) (75.6485, -1.6767) (75.2966, -1.7019) (74.9448, -1.727) (74.5929, -1.7521) (74.2409, -1.7771) (73.889, -1.802) (73.5371, -1.8269) (73.1851, -1.8516) (72.8332, -1.8763) (72.4813, -1.901) (72.1294, -1.9256) (71.7776, -1.9501) (71.4257, -1.9746) (71.0739, -1.9991) (70.7221, -2.0236) (70.3703, -2.0481) (70.0185, -2.0726) (69.6667, -2.0971) (69.3149, -2.1216) (68.9631, -2.146) (68.6113, -2.1702) (68.2594, -2.1944) (67.9075, -2.2184) (67.5557, -2.2422) (67.2038, -2.266) (66.852, -2.2897) (66.5001, -2.3133) (66.1483, -2.337) (65.7966, -2.3607) (65.4448, -2.3844) (65.0931, -2.4081) (64.7414, -2.4316) (64.3896, -2.455) (64.0378, -2.4783) (63.686, -2.5013) (63.3342, -2.5241) (62.9824, -2.5469) (62.6307, -2.5695) (62.2789, -2.592) (61.9273, -2.6145) (61.5756, -2.637) (61.2239, -2.6595) (60.8722, -2.6819) (60.5205, -2.7044) (60.1687, -2.7268) (59.8169, -2.7491) (59.4651, -2.7713) (59.1133, -2.7933) (58.7615, -2.8151) (58.4097, -2.8366) (58.058, -2.858) (57.7063, -2.8792) (57.3545, -2.9002) (57.0028, -2.9212) (56.651, -2.9422) (56.2992, -2.9632) (55.9474, -2.9841) (55.5955, -3.0049) (55.2436, -3.0257) (54.8918, -3.0462) (54.54, -3.0667) (54.1882, -3.0869) (53.8365, -3.107) (53.4847, -3.1269) (53.133, -3.1467) (52.7812, -3.1665) (52.4295, -3.1862) (52.0777, -3.2058) (51.7259, -3.2253) (51.3741, -3.2447) (51.0223, -3.2639) (50.6705, -3.283) (50.3187, -3.3019) (49.9669, -3.3207) (49.6151, -3.3393) (49.2633, -3.3578) (48.9115, -3.3761) (48.5596, -3.3943) (48.2078, -3.4124) (47.856, -3.4303) (47.5042, -3.4482) (47.1524, -3.4659) (46.8006, -3.4835) (46.4488, -3.5009) (46.097, -3.5182) (45.7451, -3.5353) (45.3932, -3.5522) (45.0412, -3.5689) (44.6892, -3.5855) (44.3371, -3.602) (43.9852, -3.6184) (43.6333, -3.6349) (43.2816, -3.6513) (42.93, -3.6676) (42.5786, -3.6839) (42.2273, -3.6999) (41.876, -3.7156) (41.5249, -3.731) (41.1738, -3.7459) (40.8227, -3.7604) (40.4717, -3.7745) (40.1207, -3.7882) (39.7697, -3.8016) (39.4187, -3.8147) (39.0677, -3.8274) (38.7168, -3.8399) (38.3659, -3.852) (38.0151, -3.8637) (37.6643, -3.875) (37.3136, -3.8858) (36.963, -3.8962) (36.6123, -3.9062) (36.2617, -3.9156) (35.9112, -3.9246) (35.5606, -3.933) (35.2101, -3.941) (34.8596, -3.9485) (34.5091, -3.9554) (34.1587, -3.9619) (33.8083, -3.968) (33.458, -3.9735) (33.1077, -3.9785) (32.7574, -3.9831) (32.4071, -3.9871) (32.0568, -3.9907) (31.7065, -3.9937) (31.3561, -3.9962) (31.0058, -3.9981) (30.6555, -3.9994) (30.3051, -4.0002) (29.9548, -4.0004) (29.6045, -4.0001) (29.2541, -3.9991) (28.9038, -3.9977) (28.5535, -3.9957) (28.2031, -3.9932) (27.8527, -3.9902) (27.5022, -3.9866) (27.1518, -3.9826) (26.8014, -3.9781) (26.4509, -3.9731) (26.1005, -3.9676) (25.7501, -3.9616) (25.3997, -3.9551) (25.0493, -3.9482) (24.6989, -3.9408) (24.3486, -3.9329) (23.9982, -3.9245) (23.648, -3.9156) (23.2977, -3.9062) (22.9475, -3.8963) (22.5973, -3.8858) (22.2471, -3.8748) (21.897, -3.8633) (21.5469, -3.8512) (21.1967, -3.8387) (20.8466, -3.8256) (20.4965, -3.8121) (20.1465, -3.798) (19.7966, -3.7833) (19.4468, -3.7681) (19.0971, -3.7523) (18.7477, -3.7359) (18.3984, -3.7188) (18.0492, -3.7011) (17.7002, -3.6829) (17.3513, -3.6639) (17.0024, -3.6444) (16.6536, -3.6242) (16.305, -3.6033) (15.9565, -3.5816) (15.6083, -3.5591) (15.2603, -3.5358) (14.9127, -3.5116) (14.5653, -3.4864) (14.2182, -3.4604) (13.8713, -3.4334) (13.5246, -3.4054) (13.1782, -3.3764) (12.8319, -3.3464) (12.4859, -3.3154) (12.1402, -3.2833) (11.7948, -3.25) (11.4497, -3.2155) (11.1051, -3.1797) (10.7609, -3.1427) (10.417, -3.1044) (10.0736, -3.0648) (9.7305, -3.0239) (9.388, -2.9816) (9.0459, -2.9379) (8.7045, -2.8927) (8.3637, -2.8461) (8.0238, -2.7979) (7.6848, -2.7482) (7.347, -2.6969) (7.0105, -2.6441) (6.6756, -2.5896) (6.3425, -2.5336) (6.0116, -2.4758) (5.6833, -2.4162) (5.3578, -2.3546) (5.0358, -2.291) (4.7179, -2.2253) (4.4046, -2.1574) (4.097, -2.0874) (3.7958, -2.0156) (3.5021, -1.9419) (3.2169, -1.8665) (2.9409, -1.7893) (2.6751, -1.7101) (2.42, -1.6289) (2.1762, -1.5453) (1.9441, -1.4597) (1.724, -1.3723) (1.516, -1.2839) (1.3201, -1.1946) (1.1361, -1.1042) (0.9639, -1.0119) (0.803, -0.9172) (0.6532, -0.821) (0.5143, -0.7255) (0.3866, -0.6316) (0.2711, -0.5345) (0.1699, -0.4251) (0.0863, -0.3012) (0.0257, -0.1765) (0.0001, -0.0919) (-0.0053, -0.0411) (-0.0028, -0.0128) (0, 0) knots 0 0 0 0 0 0 0.00333333 0.00666667 0.01 0.01333333 0.01666667 0.02 0.02333333 0.02666667 0.03 0.03333333 0.03666667 0.04 0.04333333 0.04666667 0.05 0.05333333 0.05666667 0.06 0.06333333 0.06666667 0.07 0.07333333 0.07666667 0.08 0.08333333 0.08666667 0.09 0.09333333 0.09666667 0.1 0.10333333 0.10666667 0.11 0.11333333 0.11666667 0.12 0.12333333 0.12666667 0.13 0.13333333 0.13666667 0.14 0.14333333 0.14666667 0.15 0.15333333 0.15666667 0.16 0.16333333 0.16666667 0.17 0.17333333 0.17666667 0.18 0.18333333 0.18666667 0.19 0.19333333 0.19666667 0.2 0.20333333 0.20666667 0.21 0.21333333 0.21666667 0.22 0.22333333 0.22666667 0.23 0.23333333 0.23666667 0.24 0.24333333 0.24666667 0.25 0.25333333 0.25666667 0.26 0.26333333 0.26666667 0.27 0.27333333 0.27666667 0.28 0.28333333 0.28666667 0.29 0.29333333 0.29666667 0.3 0.30333333 0.30666667 0.31 0.31333333 0.31666667 0.32 0.32333333 0.32666667 0.33 0.33333333 0.33666667 0.34 0.34333333 0.34666667 0.35 0.35333333 0.35666667 0.36 0.36333333 0.36666667 0.37 0.37333333 0.37666667 0.38 0.38333333 0.38666667 0.39 0.39333333 0.39666667 0.4 0.40333333 0.40666667 0.41 0.41333333 0.41666667 0.42 0.42333333 0.42666667 0.43 0.43333333 0.43666667 0.44 0.44333333 0.44666667 0.45 0.45333333 0.45666667 0.46 0.46333333 0.46666667 0.47 0.47333333 0.47666667 0.48 0.48333333 0.48666667 0.49 0.49333333 0.49666667 0.5 0.50333333 0.50666667 0.51 0.51333333 0.51666667 0.52 0.52333333 0.52666667 0.53 0.53333333 0.53666667 0.54 0.54333333 0.54666667 0.55 0.55333333 0.55666667 0.56 0.56333333 0.56666667 0.57 0.57333333 0.57666667 0.58 0.58333333 0.58666667 0.59 0.59333333 0.59666667 0.6 0.60333333 0.60666667 0.61 0.61333333 0.61666667 0.62 0.62333333 0.62666667 0.63 0.63333333 0.63666667 0.64 0.64333333 0.64666667 0.65 0.65333333 0.65666667 0.66 0.66333333 0.66666667 0.67 0.67333333 0.67666667 0.68 0.68333333 0.68666667 0.69 0.69333333 0.69666667 0.7 0.70333333 0.70666667 0.71 0.71333333 0.71666667 0.72 0.72333333 0.72666667 0.73 0.73333333 0.73666667 0.74 0.74333333 0.74666667 0.75 0.75333333 0.75666667 0.76 0.76333333 0.76666667 0.77 0.77333333 0.77666667 0.78 0.78333333 0.78666667 0.79 0.79333333 0.79666667 0.8 0.80333333 0.80666667 0.81 0.81333333 0.81666667 0.82 0.82333333 0.82666667 0.83 0.83333333 0.83666667 0.84 0.84333333 0.84666667 0.85 0.85333333 0.85666667 0.86 0.86333333 0.86666667 0.87 0.87333333 0.87666667 0.88 0.88333333 0.88666667 0.89 0.89333333 0.89666667 0.9 0.90333333 0.90666667 0.91 0.91333333 0.91666667 0.92 0.92333333 0.92666667 0.93 0.93333333 0.93666667 0.94 0.94333333 0.94666667 0.95 0.95333333 0.95666667 0.96 0.96333333 0.96666667 0.97 0.97333333 0.97666667 0.98 0.98333333 0.98666667 0.99 0.99333333 0.99666667 1 1 1 1 1 1
  spline S1 degree 5 poles (0, 0) (-0.0028, 0.0128) (-0.0053, 0.0411) (0.0001, 0.0919) (0.0257, 0.1765) (0.0863, 0.3012) (0.1699, 0.4251) (0.2711, 0.5345) (0.3866, 0.6316) (0.5143, 0.7255) (0.6532, 0.821) (0.803, 0.9172) (0.9639, 1.0119) (1.1361, 1.1042) (1.3201, 1.1946) (1.516, 1.2839) (1.724, 1.3723) (1.9441, 1.4597) (2.1762, 1.5453) (2.42, 1.6289) (2.6751, 1.7101) (2.9409, 1.7893) (3.2169, 1.8665) (3.5021, 1.9419) (3.7958, 2.0156) (4.097, 2.0874) (4.4046, 2.1574) (4.7179, 2.2253) (5.0358, 2.291) (5.3578, 2.3546) (5.6833, 2.4162) (6.0116, 2.4758) (6.3425, 2.5336) (6.6756, 2.5896) (7.0105, 2.6441) (7.347, 2.6969) (7.6848, 2.7482) (8.0238, 2.7979) (8.3637, 2.8461) (8.7045, 2.8927) (9.0459, 2.9379) (9.388, 2.9816) (9.7305, 3.0239) (10.0736, 3.0648) (10.417, 3.1044) (10.7609, 3.1427) (11.1051, 3.1797) (11.4497, 3.2155) (11.7948, 3.25) (12.1402, 3.2833) (12.4859, 3.3154) (12.8319, 3.3464) (13.1782, 3.3764) (13.5246, 3.4054) (13.8713, 3.4334) (14.2182, 3.4604) (14.5653, 3.4864) (14.9127, 3.5116) (15.2603, 3.5358) (15.6083, 3.5591) (15.9565, 3.5816) (16.305, 3.6033) (16.6536, 3.6242) (17.0024, 3.6444) (17.3513, 3.6639) (17.7002, 3.6829) (18.0492, 3.7011) (18.3984, 3.7188) (18.7477, 3.7359) (19.0971, 3.7523) (19.4468, 3.7681) (19.7966, 3.7833) (20.1465, 3.798) (20.4965, 3.8121) (20.8466, 3.8256) (21.1967, 3.8387) (21.5469, 3.8512) (21.897, 3.8633) (22.2471, 3.8748) (22.5973, 3.8858) (22.9475, 3.8963) (23.2977, 3.9062) (23.648, 3.9156) (23.9982, 3.9245) (24.3486, 3.9329) (24.6989, 3.9408) (25.0493, 3.9482) (25.3997, 3.9551) (25.7501, 3.9616) (26.1005, 3.9676) (26.4509, 3.9731) (26.8014, 3.9781) (27.1518, 3.9826) (27.5022, 3.9866) (27.8527, 3.9902) (28.2031, 3.9932) (28.5535, 3.9957) (28.9038, 3.9977) (29.2541, 3.9991) (29.6045, 4.0001) (29.9548, 4.0004) (30.3051, 4.0002) (30.6555, 3.9994) (31.0058, 3.9981) (31.3561, 3.9962) (31.7065, 3.9937) (32.0568, 3.9907) (32.4071, 3.9871) (32.7574, 3.9831) (33.1077, 3.9785) (33.458, 3.9735) (33.8083, 3.968) (34.1587, 3.9619) (34.5091, 3.9554) (34.8596, 3.9485) (35.2101, 3.941) (35.5606, 3.933) (35.9112, 3.9246) (36.2617, 3.9156) (36.6123, 3.9062) (36.963, 3.8962) (37.3136, 3.8858) (37.6643, 3.875) (38.0151, 3.8637) (38.3659, 3.852) (38.7168, 3.8399) (39.0677, 3.8274) (39.4187, 3.8147) (39.7697, 3.8016) (40.1207, 3.7882) (40.4717, 3.7745) (40.8227, 3.7604) (41.1738, 3.7459) (41.5249, 3.731) (41.876, 3.7156) (42.2273, 3.6999) (42.5786, 3.6839) (42.93, 3.6676) (43.2816, 3.6513) (43.6333, 3.6349) (43.9852, 3.6184) (44.3371, 3.602) (44.6892, 3.5855) (45.0412, 3.5689) (45.3932, 3.5522) (45.7451, 3.5353) (46.097, 3.5182) (46.4488, 3.5009) (46.8006, 3.4835) (47.1524, 3.4659) (47.5042, 3.4482) (47.856, 3.4303) (48.2078, 3.4124) (48.5596, 3.3943) (48.9115, 3.3761) (49.2633, 3.3578) (49.6151, 3.3393) (49.9669, 3.3207) (50.3187, 3.3019) (50.6705, 3.283) (51.0223, 3.2639) (51.3741, 3.2447) (51.7259, 3.2253) (52.0777, 3.2058) (52.4295, 3.1862) (52.7812, 3.1665) (53.133, 3.1467) (53.4847, 3.1269) (53.8365, 3.107) (54.1882, 3.0869) (54.54, 3.0667) (54.8918, 3.0462) (55.2436, 3.0257) (55.5955, 3.0049) (55.9474, 2.9841) (56.2992, 2.9631) (56.651, 2.9422) (57.0028, 2.9212) (57.3546, 2.9002) (57.7063, 2.8792) (58.058, 2.858) (58.4097, 2.8366) (58.7614, 2.8151) (59.1132, 2.7933) (59.465, 2.7713) (59.8168, 2.7491) (60.1686, 2.7268) (60.5205, 2.7044) (60.8723, 2.6819) (61.2242, 2.6595) (61.576, 2.637) (61.9277, 2.6145) (62.2795, 2.592) (62.6312, 2.5695) (62.9828, 2.5469) (63.3345, 2.5242) (63.6861, 2.5013) (64.0378, 2.4783) (64.3896, 2.455) (64.7414, 2.4316) (65.0933, 2.4081) (65.4451, 2.3844) (65.797, 2.3608) (66.1489, 2.3371) (66.5007, 2.3134) (66.8524, 2.2897) (67.2042, 2.266) (67.5559, 2.2422) (67.9076, 2.2184) (68.2594, 2.1944) (68.6111, 2.1702) (68.963, 2.146) (69.3148, 2.1216) (69.6667, 2.0971) (70.0185, 2.0726) (70.3703, 2.0481) (70.7221, 2.0236) (71.074, 1.9991) (71.4258, 1.9746) (71.7776, 1.9501) (72.1294, 1.9256) (72.4813, 1.901) (72.8332, 1.8763) (73.1851, 1.8516) (73.5371, 1.8269) (73.889, 1.802) (74.2409, 1.7771) (74.5929, 1.7521) (74.9448, 1.727) (75.2966, 1.7019) (75.6485, 1.6767) (76.0003, 1.6515) (76.3522, 1.6263) (76.704, 1.601) (77.0559, 1.5758) (77.4078, 1.5505) (77.7598, 1.5252) (78.1119, 1.5) (78.464, 1.4747) (78.8161, 1.4495) (79.1682, 1.4243) (79.5203, 1.3991) (79.8723, 1.374) (80.2243, 1.3489) (80.5763, 1.3239) (80.9282, 1.2989) (81.2802, 1.2739) (81.6322, 1.2489) (81.9842, 1.2239) (82.3362, 1.1989) (82.6882, 1.1738) (83.0402, 1.1487) (83.3921, 1.1236) (83.7441, 1.0984) (84.096, 1.0733) (84.4478, 1.0482) (84.7997, 1.0232) (85.1516, 0.9983) (85.5035, 0.9735) (85.8554, 0.9488) (86.2073, 0.9241) (86.5592, 0.8995) (86.9111, 0.8749) (87.263, 0.8502) (87.6149, 0.8254) (87.9668, 0.8006) (88.3186, 0.7759) (88.6703, 0.7512) (89.022, 0.7267) (89.3737, 0.7023) (89.7253, 0.678) (90.0769, 0.6539) (90.4285, 0.6299) (90.7802, 0.606) (91.1319, 0.5821) (91.4836, 0.5582) (91.8352, 0.5344) (92.1865, 0.5106) (92.5376, 0.4869) (92.8883, 0.4632) (93.2386, 0.4396) (93.5884, 0.4161) (93.9378, 0.3928) (94.2867, 0.3695) (94.6349, 0.3465) (94.9821, 0.3235) (95.328, 0.3008) (95.6718, 0.2783) (96.013, 0.256) (96.3507, 0.2339) (96.6841, 0.2122) (97.0124, 0.1908) (97.3347, 0.1698) (97.6501, 0.1494) (97.9576, 0.1296) (98.2562, 0.1105) (98.5446, 0.0922) (98.8215, 0.0747) (99.0859, 0.058) (99.3368, 0.0422) (99.5736, 0.0272) (99.7514, 0.0159) (99.8783, 0.0078) (99.9599, 0.0026) (100, 0) knots 0 0 0 0 0 0 0.00333333 0.00666667 0.01 0.01333333 0.01666667 0.02 0.02333333 0.02666667 0.03 0.03333333 0.03666667 0.04 0.04333333 0.04666667 0.05 0.05333333 0.05666667 0.06 0.06333333 0.06666667 0.07 0.07333333 0.07666667 0.08 0.08333333 0.08666667 0.09 0.09333333 0.09666667 0.1 0.10333333 0.10666667 0.11 0.11333333 0.11666667 0.12 0.12333333 0.12666667 0.13 0.13333333 0.13666667 0.14 0.14333333 0.14666667 0.15 0.15333333 0.15666667 0.16 0.16333333 0.16666667 0.17 0.17333333 0.17666667 0.18 0.18333333 0.18666667 0.19 0.19333333 0.19666667 0.2 0.20333333 0.20666667 0.21 0.21333333 0.21666667 0.22 0.22333333 0.22666667 0.23 0.23333333 0.23666667 0.24 0.24333333 0.24666667 0.25 0.25333333 0.25666667 0.26 0.26333333 0.26666667 0.27 0.27333333 0.27666667 0.28 0.28333333 0.28666667 0.29 0.29333333 0.29666667 0.3 0.30333333 0.30666667 0.31 0.31333333 0.31666667 0.32 0.32333333 0.32666667 0.33 0.33333333 0.33666667 0.34 0.34333333 0.34666667 0.35 0.35333333 0.35666667 0.36 0.36333333 0.36666667 0.37 0.37333333 0.37666667 0.38 0.38333333 0.38666667 0.39 0.39333333 0.39666667 0.4 0.40333333 0.40666667 0.41 0.41333333 0.41666667 0.42 0.42333333 0.42666667 0.43 0.43333333 0.43666667 0.44 0.44333333 0.44666667 0.45 0.45333333 0.45666667 0.46 0.46333333 0.46666667 0.47 0.47333333 0.47666667 0.48 0.48333333 0.48666667 0.49 0.49333333 0.49666667 0.5 0.50333333 0.50666667 0.51 0.51333333 0.51666667 0.52 0.52333333 0.52666667 0.53 0.53333333 0.53666667 0.54 0.54333333 0.54666667 0.55 0.55333333 0.55666667 0.56 0.56333333 0.56666667 0.57 0.57333333 0.57666667 0.58 0.58333333 0.58666667 0.59 0.59333333 0.59666667 0.6 0.60333333 0.60666667 0.61 0.61333333 0.61666667 0.62 0.62333333 0.62666667 0.63 0.63333333 0.63666667 0.64 0.64333333 0.64666667 0.65 0.65333333 0.65666667 0.66 0.66333333 0.66666667 0.67 0.67333333 0.67666667 0.68 0.68333333 0.68666667 0.69 0.69333333 0.69666667 0.7 0.70333333 0.70666667 0.71 0.71333333 0.71666667 0.72 0.72333333 0.72666667 0.73 0.73333333 0.73666667 0.74 0.74333333 0.74666667 0.75 0.75333333 0.75666667 0.76 0.76333333 0.76666667 0.77 0.77333333 0.77666667 0.78 0.78333333 0.78666667 0.79 0.79333333 0.79666667 0.8 0.80333333 0.80666667 0.81 0.81333333 0.81666667 0.82 0.82333333 0.82666667 0.83 0.83333333 0.83666667 0.84 0.84333333 0.84666667 0.85 0.85333333 0.85666667 0.86 0.86333333 0.86666667 0.87 0.87333333 0.87666667 0.88 0.88333333 0.88666667 0.89 0.89333333 0.89666667 0.9 0.90333333 0.90666667 0.91 0.91333333 0.91666667 0.92 0.92333333 0.92666667 0.93 0.93333333 0.93666667 0.94 0.94333333 0.94666667 0.95 0.95333333 0.95666667 0.96 0.96333333 0.96666667 0.97 0.97333333 0.97666667 0.98 0.98333333 0.98666667 0.99 0.99333333 0.99666667 1 1 1 1 1 1
  point P0 (99.197, -0.051)
  point P1 (97.999, -0.127)
  point P2 (96.426, -0.229)
  point P3 (94.627, -0.347)
  point P4 (92.758, -0.472)
  point P5 (90.868, -0.6)
  point P6 (88.975, -0.73)
  point P7 (87.08, -0.863)
  point P8 (85.184, -0.996)
  point P9 (83.288, -1.131)
  point P10 (81.391, -1.266)
  point P11 (79.494, -1.401)
  point P12 (77.596, -1.537)
  point P13 (75.7, -1.673)
  point P14 (73.804, -1.808)
  point P15 (71.908, -1.941)
  point P16 (70.013, -2.073)
  point P17 (68.118, -2.204)
  point P18 (66.223, -2.332)
  point P19 (64.329, -2.459)
  point P20 (62.435, -2.582)
  point P21 (60.542, -2.703)
  point P22 (58.648, -2.822)
  point P23 (56.755, -2.936)
  point P24 (54.861, -3.048)
  point P25 (52.968, -3.156)
  point P26 (51.075, -3.261)
  point P27 (49.182, -3.362)
  point P28 (47.289, -3.459)
  point P29 (45.396, -3.552)
  point P30 (43.502, -3.641)
  point P31 (41.614, -3.727)
  point P32 (39.73, -3.803)
  point P33 (37.848, -3.869)
  point P34 (35.969, -3.923)
  point P35 (34.092, -3.963)
  point P36 (32.217, -3.989)
  point P37 (30.342, -4)
  point P38 (28.467, -3.995)
  point P39 (26.591, -3.975)
  point P40 (24.715, -3.941)
  point P41 (22.84, -3.893)
  point P42 (20.966, -3.83)
  point P43 (19.094, -3.752)
  point P44 (17.229, -3.657)
  point P45 (15.37, -3.543)
  point P46 (13.523, -3.405)
  point P47 (11.687, -3.239)
  point P48 (9.867, -3.04)
  point P49 (8.069, -2.804)
  point P50 (6.319, -2.529)
  point P51 (4.678, -2.216)
  point P52 (3.256, -1.876)
  point P53 (2.16, -1.538)
  point P54 (1.378, -1.22)
  point P55 (0.829, -0.931)
  point P56 (0.438, -0.668)
  point P57 (0.166, -0.411)
  point P58 (0.018, -0.141)
  point P59 (0.018, 0.141)
  point P60 (0.166, 0.411)
  point P61 (0.438, 0.668)
  point P62 (0.829, 0.931)
  point P63 (1.378, 1.22)
  point P64 (2.16, 1.538)
  point P65 (3.256, 1.876)
  point P66 (4.678, 2.216)
  point P67 (6.319, 2.529)
  point P68 (8.069, 2.804)
  point P69 (9.867, 3.04)
  point P70 (11.687, 3.239)
  point P71 (13.523, 3.405)
  point P72 (15.37, 3.543)
  point P73 (17.229, 3.657)
  point P74 (19.094, 3.752)
  point P75 (20.966, 3.83)
  point P76 (22.84, 3.893)
  point P77 (24.715, 3.941)
  point P78 (26.591, 3.975)
  point P79 (28.467, 3.995)
  point P80 (30.342, 4)
  point P81 (32.217, 3.989)
  point P82 (34.092, 3.963)
  point P83 (35.969, 3.923)
  point P84 (37.848, 3.869)
  point P85 (39.73, 3.803)
  point P86 (41.614, 3.727)
  point P87 (43.502, 3.641)
  point P88 (45.396, 3.552)
  point P89 (47.289, 3.459)
  point P90 (49.182, 3.362)
  point P91 (51.075, 3.261)
  point P92 (52.968, 3.156)
  point P93 (54.861, 3.048)
  point P94 (56.755, 2.936)
  point P95 (58.648, 2.822)
  point P96 (60.542, 2.703)
  point P97 (62.436, 2.582)
  point P98 (64.329, 2.459)
  point P99 (66.224, 2.332)
  point P100 (68.118, 2.204)
  point P101 (70.013, 2.073)
  point P102 (71.908, 1.941)
  point P103 (73.804, 1.808)
  point P104 (75.7, 1.673)
  point P105 (77.596, 1.537)
  point P106 (79.494, 1.401)
  point P107 (81.391, 1.266)
  point P108 (83.288, 1.131)
  point P109 (85.184, 0.996)
  point P110 (87.08, 0.863)
  point P111 (88.975, 0.73)
  point P112 (90.868, 0.6)
  point P113 (92.758, 0.472)
  point P114 (94.627, 0.347)
  point P115 (96.426, 0.229)
  point P116 (97.999, 0.127)
  point P117 (99.197, 0.051)
surface "Schnitt_HLW_Wurzel" add patch profiles "Skizze8" section 1 separate body makes body 14
scale "Profiltiefe_HLW_Wurzel" factor 1.4 about (0, 0, 0) bodies 14